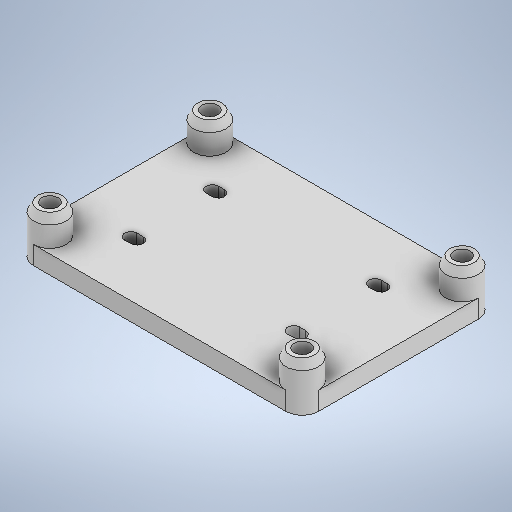
# Autodesk Inventor part: proto-board_standoffs_plate_m3
Saved by Autodesk Inventor 2025.1 (Build 291241000, 241)
## iProperties
Created: 2026-07-06
Part Number: proto-board_standoffs_plate_m3
Material: Generic
Document SubType Name: Modeling
Designer: Aiden
Density: 1 g/cm^3
Appearance: Default
Author: Aiden
Autodesk Inventor part; units mm, degrees
ref_plane "YZ Plane" through (0, 0, 0) normal (1, 0, 0) x (0, 1, 0)
ref_plane "XZ Plane" through (0, 0, 0) normal (0, 1, 0) x (-1, 0, 0)
ref_plane "XY Plane" through (0, 0, 0) normal (0, 0, 1) x (1, 0, 0)
sketch "proto-board hole layout" plane through (0, 0, 0) normal (0, 1, 0) x (-1, 0, 0)
  circle A0 centre (6.6395, -4.3647) radius 1.49
  circle A1 centre (-55.3405, -4.3647) radius 1.49
  circle A2 centre (-55.3405, 34.9153) radius 1.49
  circle A3 centre (6.6395, 34.9153) radius 1.49
  line L0 (5.1495, -4.3647) -> (-53.8505, -4.3647) construction
  line L1 (5.1495, 34.9153) -> (-53.8505, 34.9153) construction
  line L2 (-55.3405, 33.4253) -> (-55.3405, -2.8747) construction
  line L3 (6.6395, 33.4253) -> (6.6395, -2.8747) construction
  dimension "d0" = 2.98
  dimension "d1" = 59
  dimension "d2" = 36.3
  constraints: 8 end point, 8 point on circle, 4 centre point, 4 coincident, 3 equal radius, 2 horizontal alignment, 2 parallel, 2 vertical alignment, 1 horizontal, 1 perpendicular
  measures "d0" diameter of A0
  measures "d1" distance of L0.start L0.end
  measures "d2" distance of L3.start L3.end
sketch "Sketch3" plane through (0, 0, 0) normal (0, 1, 0) x (-1, 0, 0)
  circle A0 centre (6.6395, -4.3647) radius 1.49 projected
  circle A1 centre (6.6395, -4.3647) radius 4
  point P0 (0, 0)
  dimension "d15" = 8
  constraints: 1 centre point, 1 coincident
  measures "d15" diameter of A1
extrude "Extrusion2" add sketch "Sketch3" along normal blind 7 contours A0 | A1
sketch "Sketch4" plane through (-6.6395, 7, -4.3647) normal (0, 1, 0) x (1, 0, 0)
  circle A0 centre (0, 0) radius 4 construction
  point P0 (6.6395, -4.3647)
  constraints: 1 coincident
hole "Hole1" at (-6.6395, 7, -4.3647) direction (0, -1, 0) diameter 4 depth 5 tip angle 118
chamfer "Chamfer1" distance 1 distance2 2 1 edges at (-2.6395, 7, -4.3647) measured on face at (-3.1395, 7, -4.3647)
pattern_sketch "Sketch Driven Pattern1" from (-6.6395, 0, -4.3647) copies at (55.3405, 0, -4.3647) at (55.3405, 0, 34.9153) at (-6.6395, 0, 34.9153)
sketch "Sketch5" plane through (-6.6395, 0, 34.9153) normal (0, -1, 0) x (1, 0, 0)
  circle A0 centre (0, 0) radius 4 projected
  circle A1 centre (61.98, 0) radius 4 projected
  circle A2 centre (61.98, -39.28) radius 4 projected
  circle A3 centre (0, -39.28) radius 4 projected
  line L0 (-4, 4) -> (65.98, 4)
  line L1 (65.98, 4) -> (65.98, -43.28)
  line L2 (65.98, -43.28) -> (-4, -43.28)
  line L3 (-4, -43.28) -> (-4, 4)
  point P0 (6.6395, -34.9153)
  point P1 (-4, 0)
  point P2 (-4, -39.28)
  point P3 (0, -43.28)
  point P4 (61.98, -43.28)
  point P5 (65.98, -39.28)
  point P6 (65.98, 0)
  point P7 (61.98, 4)
  point P8 (0, 4)
  constraints: 8 end point, 5 tangent, 2 parallel, 1 horizontal, 1 perpendicular
extrude "Extrusion3" add sketch "Sketch5" along normal blind 4.5 contours A0 | A0 L0 A1 L1 A2 L2 A3 L3 | A1 | A3 | A2
sketch "Sketch6" plane through (-6.6395, 0, 34.9153) normal (0, 1, 0) x (1, 0, 0)
  line L0 (0, 43.28) -> (61.98, 43.28) projected
  line L1 (30.99, 43.28) -> (30.99, -4) construction
  line L2 (61.98, -4) -> (0, -4) projected
  line L3 (-4, 0) -> (-4, 39.28) projected
  line L4 (-4, 19.64) -> (65.98, 19.64) construction
  line L5 (65.98, 39.28) -> (65.98, 0) projected
  line L6 (10.24, 29.64) -> (11.74, 29.64) construction
  line L7 (10.24, 28.14) -> (11.74, 28.14)
  line L8 (11.74, 31.14) -> (10.24, 31.14)
  arc A0 (10.24, 31.14) -> (10.24, 28.14) centre (10.24, 29.64) ccw
  arc A1 (11.74, 28.14) -> (11.74, 31.14) centre (11.74, 29.64) ccw
  line L9 (65.98, 19.64) -> (-4, 19.64) construction
  line L10 (51.74, 29.64) -> (50.24, 29.64) construction
  line L11 (51.74, 28.14) -> (50.24, 28.14)
  line L12 (50.24, 31.14) -> (51.74, 31.14)
  arc A2 (51.74, 28.14) -> (51.74, 31.14) centre (51.74, 29.64) ccw
  arc A3 (50.24, 31.14) -> (50.24, 28.14) centre (50.24, 29.64) ccw
  line L13 (10.24, 9.64) -> (11.74, 9.64) construction
  line L14 (10.24, 11.14) -> (11.74, 11.14)
  line L15 (11.74, 8.14) -> (10.24, 8.14)
  arc A4 (10.24, 11.14) -> (10.24, 8.14) centre (10.24, 9.64) ccw
  arc A5 (11.74, 8.14) -> (11.74, 11.14) centre (11.74, 9.64) ccw
  line L16 (51.74, 11.14) -> (50.24, 11.14)
  arc A6 (50.24, 11.14) -> (50.24, 8.14) centre (50.24, 9.64) ccw
  line L17 (51.74, 9.64) -> (50.24, 9.64) construction
  line L18 (50.24, 8.14) -> (51.74, 8.14)
  arc A7 (51.74, 8.14) -> (51.74, 11.14) centre (51.74, 9.64) ccw
  point P0 (6.6395, 34.9153)
  point P1 (10.99, 29.64)
  point P2 (8.74, 29.64)
  point P3 (13.24, 29.64)
  point P4 (10.99, 28.14)
  point P5 (10.99, 31.14)
  point P6 (50.99, 29.64)
  point P7 (53.24, 29.64)
  point P8 (48.74, 29.64)
  point P9 (50.99, 28.14)
  point P10 (50.99, 31.14)
  point P11 (10.99, 9.64)
  point P12 (8.74, 9.64)
  point P13 (13.24, 9.64)
  point P14 (10.99, 11.14)
  point P15 (10.99, 8.14)
  point P16 (50.99, 11.14)
  point P17 (48.74, 9.64)
  point P18 (50.99, 9.64)
  point P19 (50.99, 8.14)
  point P20 (53.24, 9.64)
  dimension "d26" = 4.5
  dimension "d27" = 3
  dimension "d28" = 20
  dimension "d29" = 10
  constraints: 38 end point, 35 symmetric about line, 18 point on circle, 8 centre point, 7 midpoint, 4 tangent, 1 horizontal, 1 parallel, 6 other
  measures "d26" distance of point (8.74, 29.64) point (13.24, 29.64)
  measures "d27" distance of point (10.99, 28.14) point (10.99, 31.14)
  measures "d28" distance from line of L1 point (10.99, 29.64)
  measures "d29" distance from line of L4 point (10.99, 29.64)
extrude "Extrusion4" cut sketch "Sketch6" against normal through all
body "Solid2"
